o-ring (Autodesk Fusion 360 design; units mm, degrees)
Autodesk Fusion 360 part; units mm, degrees
sketch "Sketch1" plane through (0, 0, 0) normal (0, 1, 0) x (1, 0, 0)
  line L0 (20.2, -12.675) -> (-20.2, -12.675)
  line L1 (-20.2, -12.675) -> (-20.2, 12.675)
  line L2 (-20.2, 12.675) -> (20.2, 12.675)
  line L3 (20.2, 12.675) -> (20.2, -12.675)
  line L4 (20.2, -12.675) -> (-20.2, 12.675) construction
  line L5 (-20.2, -12.675) -> (20.2, 12.675) construction
  line L6 (19.2, -11.675) -> (-19.2, -11.675)
  line L7 (-19.2, -11.675) -> (-19.2, 11.675)
  line L8 (-19.2, 11.675) -> (19.2, 11.675)
  line L9 (19.2, 11.675) -> (19.2, -11.675)
  line L10 (19.2, -11.675) -> (-19.2, 11.675) construction
  line L11 (-19.2, -11.675) -> (19.2, 11.675) construction
  dimension "d1" = 25.35
  dimension "d2" = 40.4
  dimension "d3" = 38.4
  dimension "d4" = 23.35
  constraint perpendicular L0 L1
  constraint parallel L0 L2
  constraint parallel L1 L3
  constraint horizontal L0
  constraint coincident L4 origin
  constraint coincident L5 origin
  constraint perpendicular L6 L7
  constraint parallel L6 L8
  constraint parallel L7 L9
  constraint horizontal L6
  constraint coincident L10 origin
  constraint coincident L11 origin
  measures "d1" distance of L0.end L1.end
  measures "d2" distance of L1.end L2.end
  measures "d3" distance of L7.end L8.end
  measures "d4" distance of L6.end L7.end
extrude "Extrude1" add sketch "Sketch1" along normal blind 2.5
fillet "Fillet1" radius 2.5 8 edges at (-19.2, 1.25, -11.675) (19.2, 1.25, -11.675) (19.2, 1.25, 11.675) (-19.2, 1.25, 11.675) (20.2, 1.25, -12.675) (-20.2, 1.25, -12.675) (-20.2, 1.25, 12.675) (20.2, 1.25, 12.675)
